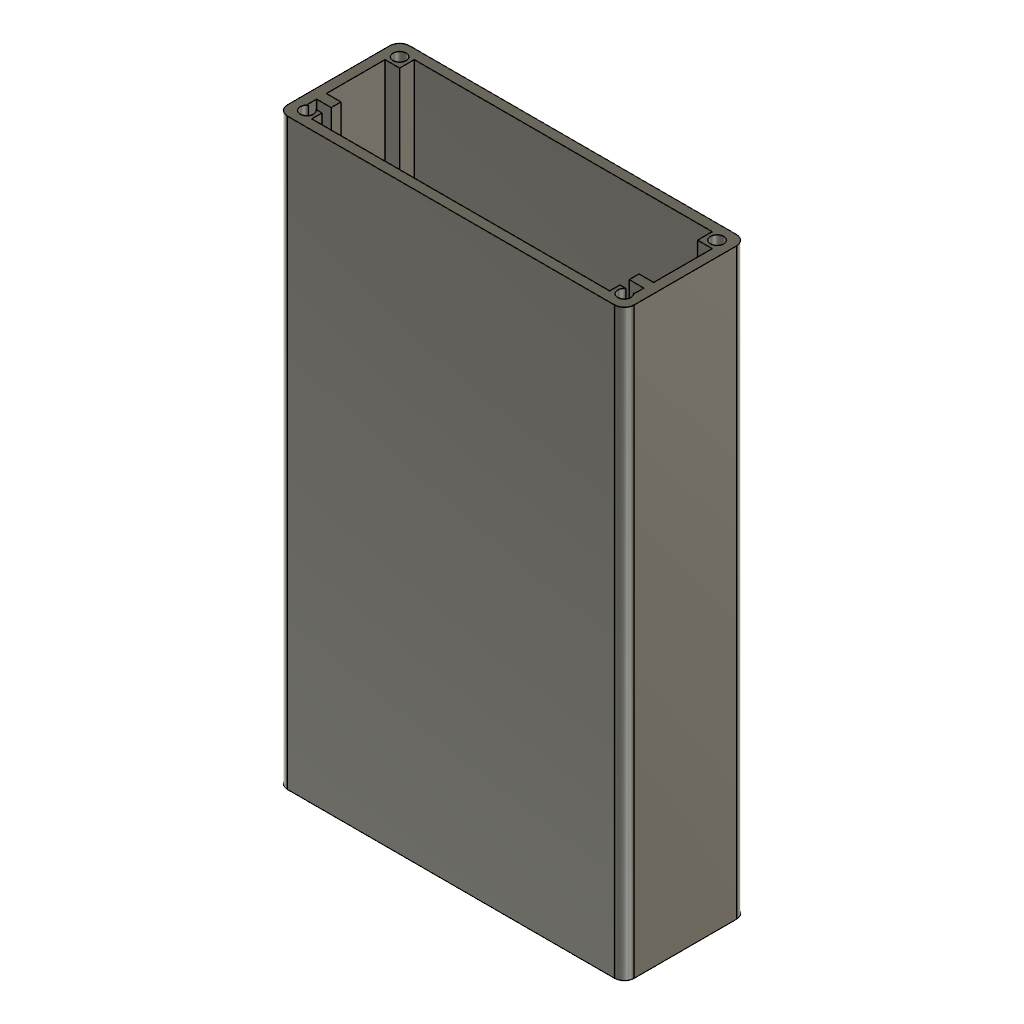
gg-sleeve-case (Autodesk Fusion 360 design; units mm, degrees)
Autodesk Fusion 360 part; units mm, degrees
sketch "Skizze1" plane through (0, 0, 0) normal (0, 0, 1) x (1, 0, 0)
  line L0 (2, 0) -> (69, 0)
  line L1 (71, 2) -> (71, 23)
  line L2 (69, 25) -> (2, 25)
  line L3 (0, 23) -> (0, 2)
  arc A0 (2, 25) -> (0, 23) centre (2, 23) ccw
  arc A1 (0, 2) -> (2, 0) centre (2, 2) ccw
  arc A2 (71, 23) -> (69, 25) centre (69, 23) ccw
  arc A3 (69, 0) -> (71, 2) centre (69, 2) ccw
  point P0 (71, 0)
  point P1 (0, 25)
  dimension "d1" = 25
  dimension "d2" = 71
  dimension "d3" = 2
  dimension "d4" = 2
  dimension "d5" = 2
  dimension "d6" = 2
  constraint horizontal L0
  constraint vertical L1
  constraint horizontal L2
  constraint vertical L3
  constraint coincident P1 L2
  constraint coincident P1 L3
  constraint tangent L2 A0
  constraint tangent L3 A0
  constraint coincident origin L0
  constraint coincident origin L3
  constraint tangent L0 A1
  constraint tangent L3 A1
  constraint tangent L1 A2
  constraint tangent L2 A2
  constraint coincident P0 L0
  constraint coincident P0 L1
  constraint tangent L0 A3
  constraint tangent L1 A3
  measures "d1" distance of origin P1
  measures "d2" distance of origin P0
  measures "d3" radius of A0
  measures "d4" radius of A1
  measures "d5" radius of A2
  measures "d6" radius of A3
extrude "Extrusion1" add sketch "Skizze1" along normal blind 3.4 makes body 1
sketch "Skizze2" plane through (0, 0, 3.4) normal (0, 0, 1) x (-1, 0, 0)
  arc A0 (-69, 0) -> (-71, -2) centre (-69, -2) ccw
  line L0 (-71, -2) -> (-71, -23)
  arc A1 (-71, -23) -> (-69, -25) centre (-69, -23) ccw
  line L1 (-69, -25) -> (-2, -25)
  arc A2 (-2, -25) -> (0, -23) centre (-2, -23) ccw
  line L2 (0, -23) -> (0, -2)
  arc A3 (0, -2) -> (-2, 0) centre (-2, -2) ccw
  line L3 (-2, 0) -> (-69, 0)
  line L4 (-28.5, -17.5) -> (-37.5, -17.5)
  line L5 (-37.5, -17.5) -> (-37.5, -6)
  line L6 (-37.5, -6) -> (-28.5, -6)
  line L7 (-28.5, -6) -> (-28.5, -17.5)
  dimension "d9" = 6
  dimension "d10" = 11.5
  dimension "d11" = 9
  dimension "d12" = 33.5
  dimension "d13" = 28.5
  dimension "d14" = 7.5
  constraint horizontal L4
  constraint vertical L5
  constraint horizontal L6
  constraint vertical L7
  measures "d9" vertical distance of origin L6.end
  measures "d10" distance of L4.start L6.end
  measures "d11" distance of L5.end L6.end
  measures "d12" horizontal distance of A0.end L5.end
  measures "d13" horizontal distance of L2.end L6.end
  measures "d14" vertical distance of L1.end L4.start
extrude "Extrusion2" cut sketch "Skizze2" against normal through all contours L4 L5 L6 L7 bodies 1
sketch "Skizze4" plane through (0, 0, 3.4) normal (0, 0, 1) x (-1, 0, 0)
  line L0 (-28.5, -6) -> (-28.5, -17.5)
  line L1 (-28.5, -17.5) -> (-37.5, -17.5)
  line L2 (-37.5, -17.5) -> (-37.5, -6)
  line L3 (-37.5, -6) -> (-28.5, -6)
  arc A0 (-69, 0) -> (-71, -2) centre (-69, -2) ccw
  line L4 (-71, -2) -> (-71, -23)
  arc A1 (-71, -23) -> (-69, -25) centre (-69, -23) ccw
  line L5 (-69, -25) -> (-2, -25)
  arc A2 (-2, -25) -> (0, -23) centre (-2, -23) ccw
  line L6 (0, -23) -> (0, -2)
  arc A3 (0, -2) -> (-2, 0) centre (-2, -2) ccw
  line L7 (-2, 0) -> (-69, 0)
  line L8 (-2, 0) -> (-69, 0)
  line L9 (-71, -2) -> (-71, -23)
  line L10 (-69, -25) -> (-2, -25)
  line L11 (0, -23) -> (0, -2)
  arc A4 (0, -2) -> (-2, 0) centre (-2, -2) ccw
  arc A5 (-2, -25) -> (0, -23) centre (-2, -23) ccw
  arc A6 (-71, -23) -> (-69, -25) centre (-69, -23) ccw
  arc A7 (-69, 0) -> (-71, -2) centre (-69, -2) ccw
  line L12 (-4, -23) -> (-67, -23)
  line L13 (-69, -21) -> (-69, -4)
  line L14 (-67, -2) -> (-4, -2)
  line L15 (-2, -4) -> (-2, -21)
  arc A8 (-4, -23) -> (-2, -21) centre (-4, -21) ccw
  arc A9 (-2, -4) -> (-4, -2) centre (-4, -4) ccw
  arc A10 (-67, -2) -> (-69, -4) centre (-67, -4) ccw
  arc A11 (-69, -21) -> (-67, -23) centre (-67, -21) ccw
  dimension "d16" = 2
  dimension "d17" = 2
  dimension "d18" = 2
  dimension "d19" = 2
  dimension "d20" = 2
  dimension "d21" = 2
  dimension "d22" = 2
  dimension "d23" = 2
  dimension "d24" = 2
  dimension "d25" = 2
  dimension "d26" = 2
  dimension "d27" = 2
  constraint horizontal L8
  constraint vertical L9
  constraint horizontal L10
  constraint vertical L11
  constraint tangent L8 A4
  constraint tangent L11 A4
  constraint tangent L10 A5
  constraint tangent L11 A5
  constraint tangent L9 A6
  constraint tangent L10 A6
  constraint tangent L8 A7
  constraint tangent L9 A7
  constraint coincident A1.end L5.start
  constraint coincident A3.end L7.start
  constraint horizontal L12
  constraint vertical L13
  constraint horizontal L14
  constraint vertical L15
  constraint tangent L12 A8
  constraint tangent L15 A8
  constraint tangent L14 A9
  constraint tangent L15 A9
  constraint tangent L13 A10
  constraint tangent L14 A10
  constraint tangent L12 A11
  constraint tangent L13 A11
  measures "d16" radius of A4
  measures "d17" radius of A5
  measures "d18" radius of A6
  measures "d19" radius of A7
  measures "d20" radius of A8
  measures "d21" radius of A9
  measures "d22" radius of A10
  measures "d23" radius of A11
  measures "d24" vertical distance of A3.centre A9.centre
  measures "d25" horizontal distance of A3.centre A9.centre
  measures "d26" vertical distance of A2.centre A8.centre
  measures "d27" horizontal distance of A0.centre A10.centre
extrude "Extrusion3" add sketch "Skizze4" along normal blind 116 contours A0 L4 A1 L5 A2 L6 A3 L7 L8 L9 L10 L11 A4 A5 A6 A7 bodies 1
sketch "Skizze5" plane through (0, 0, 119.4) normal (0, 0, 1) x (-1, 0, 0)
  arc A0 (-67, -2) -> (-69, -4) centre (-67, -4) ccw
  line L0 (-67, -2) -> (-4, -2)
  arc A1 (-2, -4) -> (-4, -2) centre (-4, -4) ccw
  line L1 (-2, -4) -> (-2, -21)
  arc A2 (-4, -23) -> (-2, -21) centre (-4, -21) ccw
  line L2 (-4, -23) -> (-67, -23)
  arc A3 (-69, -21) -> (-67, -23) centre (-67, -21) ccw
  line L3 (-69, -21) -> (-69, -4)
  arc A4 (-69, 0) -> (-71, -2) centre (-69, -2) ccw
  line L4 (-71, -2) -> (-71, -23)
  arc A5 (-71, -23) -> (-69, -25) centre (-69, -23) ccw
  line L5 (-69, -25) -> (-2, -25)
  arc A6 (-2, -25) -> (0, -23) centre (-2, -23) ccw
  line L6 (0, -23) -> (0, -2)
  arc A7 (0, -2) -> (-2, 0) centre (-2, -2) ccw
  line L7 (-2, 0) -> (-69, 0)
  line L8 (-2, 0) -> (-5, 0)
  line L9 (-5, 0) -> (-5, -4.1)
  line L10 (-5, -4.1) -> (-2, -4.1)
  line L11 (-2, -4.1) -> (-2, 0)
  line L12 (-69, 0) -> (-66, 0)
  line L13 (-66, 0) -> (-66, -4.1)
  line L14 (-66, -4.1) -> (-69, -4.1)
  line L15 (-69, -4.1) -> (-69, 0)
  line L16 (-2, -8) -> (-5, -8)
  line L17 (-5, -8) -> (-5, -6)
  line L18 (-5, -6) -> (-2, -6)
  line L19 (-2, -6) -> (-2, -8)
  line L20 (-66, -8) -> (-69, -8)
  line L21 (-69, -8) -> (-69, -6)
  line L22 (-69, -6) -> (-66, -6)
  line L23 (-66, -6) -> (-66, -8)
  line L24 (-2, -23) -> (-5, -23)
  line L25 (-5, -23) -> (-5, -20)
  line L26 (-5, -20) -> (-2, -20)
  line L27 (-2, -20) -> (-2, -23)
  line L28 (-69, -23) -> (-66, -23)
  line L29 (-66, -23) -> (-66, -20)
  line L30 (-66, -20) -> (-69, -20)
  line L31 (-69, -20) -> (-69, -23)
  point P0 (-28.5, -6)
  point P1 (-37.5, -6)
  dimension "d30" = 1.9
  dimension "d31" = 3
  dimension "d32" = 3
  dimension "d34" = 2
  dimension "d35" = 2
  dimension "d37" = 3
  dimension "d78" = 67
  constraint horizontal L8
  constraint vertical L9
  constraint horizontal L10
  constraint vertical L11
  constraint coincident A7.end L7.start
  constraint horizontal L12
  constraint vertical L13
  constraint horizontal L14
  constraint vertical L15
  constraint coincident A4.start L7.end
  constraint horizontal L9.end L13.end
  constraint horizontal L16
  constraint vertical L17
  constraint horizontal L18
  constraint vertical L19
  constraint coincident L1 L16.start
  constraint horizontal L20
  constraint vertical L21
  constraint horizontal L22
  constraint vertical L23
  constraint coincident L3 L21.end
  constraint vertical L9.end L17.end
  constraint vertical L13.end L22.end
  constraint horizontal P0 L17.end
  constraint horizontal L22.end P1
  constraint horizontal L24
  constraint vertical L25
  constraint horizontal L26
  constraint vertical L27
  constraint coincident A6.centre L24.start
  constraint horizontal L28
  constraint vertical L29
  constraint horizontal L30
  constraint vertical L31
  constraint coincident A5.centre L28.start
  constraint vertical L16.end L25.end
  constraint vertical L20.start L29.end
  constraint horizontal L25.end L29.end
  measures "d30" vertical distance of L9.end P0
  measures "d31" horizontal distance of A7.end L9.end
  measures "d32" horizontal distance of A0.end L13.end
  measures "d34" distance of L16.end L17.end
  measures "d35" distance of L20.start L22.end
  measures "d37" distance of A6.centre L26.end
  measures "d78" distance of L18.end L21.end
extrude "Extrusion4" add sketch "Skizze5" against normal through all of body 1 contours A0 L0 L3 L13 L14 L15 | L0 A1 L1 L9 L10 L11 | L3 L20 L21 L22 L23 | L2 A3 L3 L28 L29 L30 L31 | L1 L16 L17 L18 L19 | L1 A2 L2 L24 L25 L26 L27 bodies 1
sketch "Skizze6" plane through (0, 0, 119.4) normal (0, 0, 1) x (-1, 0, 0)
  line L0 (-66, -2) -> (-5, -2)
  line L1 (-5, -2) -> (-5, -4.1)
  line L2 (-5, -4.1) -> (-2, -4.1)
  line L3 (-2, -4.1) -> (-2, -6)
  line L4 (-2, -6) -> (-5, -6)
  line L5 (-5, -6) -> (-5, -8)
  line L6 (-5, -8) -> (-2, -8)
  line L7 (-2, -8) -> (-2, -20)
  line L8 (-2, -20) -> (-5, -20)
  line L9 (-5, -20) -> (-5, -23)
  line L10 (-5, -23) -> (-66, -23)
  line L11 (-66, -23) -> (-66, -20)
  line L12 (-66, -20) -> (-69, -20)
  line L13 (-69, -20) -> (-69, -8)
  line L14 (-69, -8) -> (-66, -8)
  line L15 (-66, -8) -> (-66, -6)
  line L16 (-66, -6) -> (-69, -6)
  line L17 (-69, -6) -> (-69, -4.1)
  line L18 (-69, -4.1) -> (-66, -4.1)
  line L19 (-66, -4.1) -> (-66, -2)
  arc A0 (-69, 0) -> (-71, -2) centre (-69, -2) ccw
  line L20 (-71, -2) -> (-71, -23)
  arc A1 (-71, -23) -> (-69, -25) centre (-69, -23) ccw
  line L21 (-69, -25) -> (-2, -25)
  arc A2 (-2, -25) -> (0, -23) centre (-2, -23) ccw
  line L22 (0, -23) -> (0, -2)
  arc A3 (0, -2) -> (-2, 0) centre (-2, -2) ccw
  line L23 (-2, 0) -> (-69, 0)
  line L24 (-2, -25) -> (-69, -25)
  line L25 (-71, -23) -> (-71, -2)
  line L26 (-69, 0) -> (-2, 0)
  line L27 (0, -2) -> (0, -23)
  arc A4 (0, -2) -> (-2, 0) centre (-2, -2) ccw
  arc A5 (-2, -25) -> (0, -23) centre (-2, -23) ccw
  arc A6 (-71, -23) -> (-69, -25) centre (-69, -23) ccw
  arc A7 (-69, 0) -> (-71, -2) centre (-69, -2) ccw
  dimension "d38" = 2
  dimension "d39" = 2
  dimension "d40" = 2
  dimension "d41" = 2
  constraint horizontal L24
  constraint vertical L25
  constraint horizontal L26
  constraint vertical L27
  constraint tangent L26 A4
  constraint tangent L27 A4
  constraint tangent L24 A5
  constraint tangent L27 A5
  constraint tangent L24 A6
  constraint tangent L25 A6
  constraint tangent L25 A7
  constraint tangent L26 A7
  constraint coincident A1.centre A6.centre
  constraint coincident A3.centre A4.centre
  measures "d38" radius of A4
  measures "d39" radius of A5
  measures "d40" radius of A6
  measures "d41" radius of A7
extrude "Extrusion5" add sketch "Skizze6" along normal blind 3.4 separate body contours L0 L1 L2 L3 L4 L5 L6 L7 L8 L9 L10 L11 L12 L13 L14 L15 L16 L17 L18 L19 | A0 L20 A1 L21 A2 L22 A3 L23 L24 L25 L26 L27 A4 A5 A6 A7 makes body 2
sketch "Skizze7" plane through (0, 0, 122.8) normal (0, 0, 1) x (-1, 0, 0)
  arc A0 (0, -2) -> (-2, 0) centre (-2, -2) ccw
  line L0 (-2, 0) -> (-69, 0)
  arc A1 (-69, 0) -> (-71, -2) centre (-69, -2) ccw
  line L1 (-71, -2) -> (-71, -23)
  arc A2 (-71, -23) -> (-69, -25) centre (-69, -23) ccw
  line L2 (-69, -25) -> (-2, -25)
  arc A3 (-2, -25) -> (0, -23) centre (-2, -23) ccw
  line L3 (0, -23) -> (0, -2)
  circle A4 centre (-3, -22) radius 1.35
  circle A5 centre (-68, -22) radius 1.35
  circle A6 centre (-3, -3) radius 1.35
  circle A7 centre (-68, -3) radius 1.35
  circle A8 centre (-8, -13) radius 3.25
  circle A9 centre (-63, -13) radius 3.25
  dimension "d44" = 2.7
  dimension "d45" = 3
  dimension "d46" = 3
  dimension "d47" = 3
  dimension "d48" = 3
  dimension "d51" = 6.5
  dimension "d52" = 13
  dimension "d53" = 8
  dimension "d54" = 8
  dimension "d55" = 55
  constraint equal A4 A5
  constraint equal A4 A7
  constraint equal A4 A6
  constraint vertical A4.centre A6.centre
  constraint horizontal A4.centre A5.centre
  constraint horizontal A6.centre A7.centre
  constraint vertical A5.centre A7.centre
  constraint equal A8 A9
  constraint horizontal A8.centre A9.centre
  measures "d44" diameter of A4
  measures "d45" horizontal distance of A3.end A4.centre
  measures "d46" vertical distance of L2.end A4.centre
  measures "d47" horizontal distance of L1.end A5.centre
  measures "d48" vertical distance of origin A6.centre
  measures "d51" diameter of A8
  measures "d52" vertical distance of origin A8.centre
  measures "d53" horizontal distance of origin A8.centre
  measures "d54" horizontal distance of A1.end A9.centre
  measures "d55" distance of A8.centre A9.centre
extrude "Extrusion6" cut sketch "Skizze7" against normal blind 10 contours A4 | A5 | A6 | A7 | A8 | A9 bodies 1 2
sketch "Skizze8" plane through (0, 0, 122.8) normal (0, 0, 1) x (-1, 0, 0)
  arc A0 (0, -2) -> (-2, 0) centre (-2, -2) ccw
  line L0 (-2, 0) -> (-69, 0)
  arc A1 (-69, 0) -> (-71, -2) centre (-69, -2) ccw
  line L1 (-71, -2) -> (-71, -23)
  arc A2 (-71, -23) -> (-69, -25) centre (-69, -23) ccw
  line L2 (-69, -25) -> (-2, -25)
  arc A3 (-2, -25) -> (0, -23) centre (-2, -23) ccw
  line L3 (0, -23) -> (0, -2)
  circle A4 centre (-63, -13) radius 3.25
  circle A5 centre (-3, -22) radius 1.35
  circle A6 centre (-3, -3) radius 1.35
  circle A7 centre (-8, -13) radius 3.25
  circle A8 centre (-68, -22) radius 1.35
  circle A9 centre (-68, -3) radius 1.35
  circle A10 centre (-3, -22) radius 2.75
  circle A11 centre (-68, -22) radius 2.75
  circle A12 centre (-68, -3) radius 2.75
  circle A13 centre (-3, -3) radius 2.75
  dimension "d56" = 5.5
  constraint concentric A5 A10
  constraint concentric A8 A11
  constraint concentric A9 A12
  constraint concentric A6 A13
  constraint equal A10 A13
  constraint equal A10 A11
  constraint equal A11 A12
  measures "d56" diameter of A10
extrude "Extrusion7" cut sketch "Skizze8" against normal blind 2 contours A10 | A11 | A12 | A13 bodies 2
sketch "Skizze9" plane through (0, 0, 122.8) normal (0, 0, 1) x (-1, 0, 0)
  circle A0 centre (-8, -13) radius 3.25
  circle A1 centre (-63, -13) radius 3.25
  arc A2 (0, -2) -> (-2, 0) centre (-2, -2) ccw
  line L0 (-2, 0) -> (-69, 0)
  arc A3 (-69, 0) -> (-71, -2) centre (-69, -2) ccw
  line L1 (-71, -2) -> (-71, -23)
  arc A4 (-71, -23) -> (-69, -25) centre (-69, -23) ccw
  line L2 (-69, -25) -> (-2, -25)
  arc A5 (-2, -25) -> (0, -23) centre (-2, -23) ccw
  line L3 (0, -23) -> (0, -2)
  circle A6 centre (-68, -3) radius 2.75
  circle A7 centre (-3, -3) radius 2.75
  circle A8 centre (-68, -22) radius 2.75
  circle A9 centre (-3, -22) radius 2.75
  line L4 (-10, 0) -> (-25, 0)
  line L5 (-25, 0) -> (-25, -3)
  line L6 (-25, -3) -> (-10, -3)
  line L7 (-10, -3) -> (-10, 0)
  line L8 (-61, 0) -> (-46, 0)
  line L9 (-46, 0) -> (-46, -3)
  line L10 (-46, -3) -> (-61, -3)
  line L11 (-61, -3) -> (-61, 0)
  dimension "d59" = 10
  dimension "d60" = 10
  dimension "d61" = 15
  dimension "d62" = 3
  constraint horizontal L4
  constraint vertical L5
  constraint horizontal L6
  constraint vertical L7
  constraint coincident L0 L4.start
  constraint horizontal L8
  constraint vertical L9
  constraint horizontal L10
  constraint vertical L11
  constraint coincident L0 L8.start
  constraint equal L4 L8
  constraint horizontal L5.end L9.end
  measures "d59" distance of origin L4.start
  measures "d60" horizontal distance of A3.end L8.start
  measures "d61" distance of L4.start L4.end
  measures "d62" distance of L4.start L6.end
extrude "Extrusion8" add sketch "Skizze9" along normal blind 15 contours L0 L4 L5 L6 L7 | L0 L8 L9 L10 L11 bodies 2
fillet "Abrundung1" radius 2 1 edges at (61, 1.5, 137.8) on bodies 2
fillet "Abrundung2" radius 2 1 edges at (46, 1.5, 137.8) on bodies 2
fillet "Abrundung3" radius 2 1 edges at (10, 1.5, 137.8) on bodies 2
fillet "Abrundung4" radius 2 1 edges at (25, 1.5, 137.8) on bodies 2
sketch "Skizze10" plane through (0, 3, 0) normal (0, 1, 0) x (-1, 0, 0)
  arc A0 (-46, 135.8) -> (-48, 137.8) centre (-48, 135.8) ccw
  line L0 (-48, 137.8) -> (-59, 137.8)
  arc A1 (-59, 137.8) -> (-61, 135.8) centre (-59, 135.8) ccw
  line L1 (-61, 135.8) -> (-61, 122.8)
  line L2 (-61, 122.8) -> (-46, 122.8)
  line L3 (-46, 122.8) -> (-46, 135.8)
  circle A2 centre (-17.5, 130.3) radius 3
  circle A3 centre (-53.5, 130.3) radius 3
  point P0 (-10, 122.8)
  dimension "d73" = 7.5
  dimension "d74" = 7.5
  dimension "d75" = 7.5
  dimension "d76" = 6
  constraint horizontal A2.centre A3.centre
  constraint equal A2 A3
  measures "d73" vertical distance of A2.centre P0
  measures "d74" horizontal distance of A2.centre P0
  measures "d75" horizontal distance of L2.end A3.centre
  measures "d76" diameter of A2
extrude "Extrusion9" cut sketch "Skizze10" against normal through all contours A2 | A3 bodies 2
hidden bodies 2
